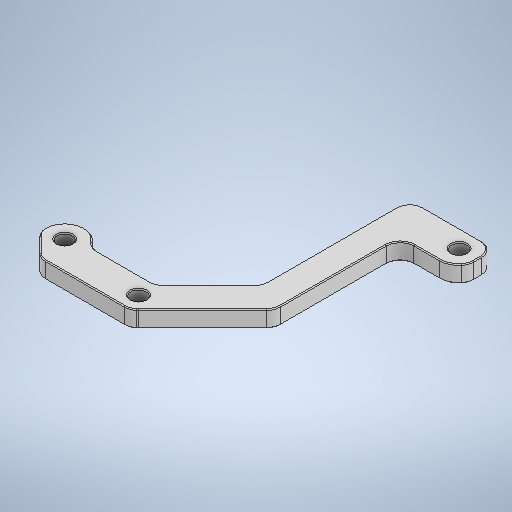
# Autodesk Inventor part: Separator
Saved by Autodesk Inventor 2025.2 (Build 292293000, 293)
## iProperties
Created: 2026-06-16
Part Number: Separator
Material: Generic
Document SubType Name: Modeling
Designer: Bruno
Density: 1 g/cm^3
Appearance: Default
Author: Bruno
## iProperties of the stored document Separator_3DPrint.ipt
Created: 2026-06-26
Part Number: Separator_3DPrint
Material: Generic
Document SubType Name: Modeling
Designer: Bruno
Density: 1 g/cm^3
Appearance: Default
Author: Bruno
Autodesk Inventor part; units mm, degrees
ref_plane "YZ Plane" through (0, 0, 0) normal (1, 0, 0) x (0, 1, 0)
ref_plane "XZ Plane" through (0, 0, 0) normal (0, 1, 0) x (-1, 0, 0)
ref_plane "XY Plane" through (0, 0, 0) normal (0, 0, 1) x (1, 0, 0)
sketch "Sketch1" plane through (0, 0, 0) normal (0, 1, 0) x (-1, 0, 0)
  line L0 (58.4, 33.4) -> (-58.4, 33.4) construction
  line L1 (-58.4, 33.4) -> (-58.4, -33.4)
  line L2 (-58.4, -33.4) -> (58.4, -33.4)
  line L3 (58.4, -33.4) -> (58.4, 33.4)
  line L4 (58.4, 33.4) -> (-58.4, -33.4) construction
  line L5 (-58.4, 33.4) -> (58.4, -33.4) construction
  line L6 (58.4, 33.4) -> (58.4, 88.4)
  line L7 (58.4, 88.4) -> (-58.4, 88.4)
  line L8 (-58.4, 88.4) -> (-58.4, 33.4)
  line L9 (20.8, 25.375) -> (-25.45, 25.375) construction
  line L10 (-25.45, 25.375) -> (-26.8, 24.025) construction
  line L11 (-26.8, 24.025) -> (-26.8, -24.025) construction
  line L12 (-26.8, -24.025) -> (-25.45, -25.375) construction
  line L13 (-25.45, -25.375) -> (20.8, -25.375) construction
  line L14 (20.8, -25.375) -> (26.8, -19.375) construction
  line L15 (26.8, -19.375) -> (26.8, 19.375) construction
  line L16 (26.8, 19.375) -> (20.8, 25.375) construction
  line L17 (0, 0) -> (14.4314, 0) construction
  line L18 (0, 0) -> (0, -12.5097) construction
  line L19 (20.8828, 25.575) -> (-25.5328, 25.575)
  line L20 (-25.5328, 25.575) -> (-27, 24.1078)
  line L21 (-27, 24.1078) -> (-27, -24.1078)
  line L22 (-27, -24.1078) -> (-25.5328, -25.575)
  line L23 (-25.5328, -25.575) -> (20.8828, -25.575)
  line L24 (20.8828, -25.575) -> (27, -19.4578)
  line L25 (27, -19.4578) -> (27, 19.4578) construction
  line L26 (27, 19.4578) -> (20.8828, 25.575)
  arc A0 (-27, -24.1078) -> (-25.5328, -25.575) centre (-25.5328, -24.1078) ccw
  arc A1 (-25.5328, 25.575) -> (-27, 24.1078) centre (-25.5328, 24.1078) ccw
  line L27 (29.5, -16.9578) -> (29.5, 16.9578)
  line L28 (27, -19.4578) -> (29.5, -16.9578)
  line L29 (27, 19.4578) -> (29.5, 16.9578)
  dimension "d0" = 116.8
  dimension "d1" = 66.8
  dimension "d2" = 121.8
  dimension "d6" = 50.75
  dimension "d7" = 53.6
  dimension "d8" = 50.75
  dimension "d9" = 53.6
  dimension "d10" = 45
  dimension "d11" = 48.05
  dimension "d12" = 38.75
  dimension "d13" = 0.2
  dimension "d19" = 2.7
  constraints: 60 end point, 10 perpendicular, 6 parallel, 4 point on circle, 3 equal length, 3 horizontal, 3 vertical, 2 centre point, 2 midpoint, 2 tangent, 1 collinear, 7 other
  measures "d0" distance of L1.end L2.end
  measures "d1" distance between parallel lines of L2 L0
  measures "d2" distance between parallel lines of L2 L7
  measures "d6" distance between parallel lines of L13 L9
  measures "d7" distance between parallel lines of L11 L15
  measures "d8" diameter of L9 L17
  measures "d9" diameter of L15 L18
  measures "d10" angle of L11 L12
  measures "d11" distance of L10.end L11.end
  measures "d12" distance of L14.end L15.end
  measures "d13" distance between parallel lines of L16 L26
  measures "d19" distance between parallel lines of L15 L27
extrude "Extrusion1" add sketch "Sketch1" along normal blind 1.6 contours L8 L7 L6 L3 L2 L1 | L20 A1 | L22 A0
sketch "Sketch2" plane through (0, 0, 0) normal (0, -1, 0) x (1, 0, 0)
  line L0 (58.4, -33.4) -> (-58.4, -33.4) projected
  line L1 (58.4, 88.4) -> (58.4, -33.4) projected
  line L2 (-58.4, 88.4) -> (58.4, 88.4) projected
  line L3 (-58.4, -33.4) -> (-58.4, 88.4) projected
  line L4 (25.5328, -25.575) -> (27, -24.1078) projected
  line L5 (-20.8828, -25.575) -> (25.5328, -25.575) projected
  line L6 (-29.5, -16.9578) -> (-20.8828, -25.575) projected
  line L7 (-29.5, 16.9578) -> (-29.5, -16.9578) projected
  line L8 (-20.8828, 25.575) -> (-29.5, 16.9578) projected
  line L9 (25.5328, 25.575) -> (-20.8828, 25.575) projected
  line L10 (27, 24.1078) -> (25.5328, 25.575) projected
  line L11 (27, -24.1078) -> (27, 24.1078) projected
  line L12 (-21.5456, 27.175) -> (-31.1, 17.6206)
  line L13 (-31.1, 17.6206) -> (-31.1, -17.6206)
  line L14 (-31.1, -17.6206) -> (-21.5456, -27.175)
  line L15 (-21.5456, -27.175) -> (26.1956, -27.175)
  line L16 (26.1956, -27.175) -> (28.6, -24.7706)
  line L17 (28.6, -24.7706) -> (28.6, 24.7706)
  line L18 (28.6, 24.7706) -> (26.1956, 27.175)
  line L19 (26.1956, 27.175) -> (-21.5456, 27.175)
  dimension "d77" = 1.6
  constraints: 16 end point, 7 other
  measures "d77" distance between parallel lines of L9 L19
extrude "Extrusion2" add sketch "Sketch2" along normal blind 25.235 contours L19 L18 L17 L16 L15 L14 L13 L12
sketch "Sketch3" plane through (0, -25.235, 0) normal (0, -1, 0) x (1, 0, 0)
  line L0 (-31.1, 17.6206) -> (-31.1, -17.6206) projected
  line L1 (-31.1, -17.6206) -> (-21.5456, -27.175) projected
  line L2 (-21.5456, -27.175) -> (26.1956, -27.175) projected
  line L3 (26.1956, -27.175) -> (28.6, -24.7706) projected
  line L4 (28.6, -24.7706) -> (28.6, 24.7706) projected
  line L5 (28.6, 24.7706) -> (26.1956, 27.175) projected
  line L6 (26.1956, 27.175) -> (-21.5456, 27.175) projected
  line L7 (-21.5456, 27.175) -> (-31.1, 17.6206) projected
  line L8 (25.5328, -25.575) -> (-20.8828, -25.575) projected
  line L9 (-20.8828, -25.575) -> (-29.5, -16.9578) projected
  line L10 (-29.5, -16.9578) -> (-29.5, 16.9578) projected
  line L11 (-29.5, 16.9578) -> (-20.8828, 25.575) projected
  line L12 (-20.8828, 25.575) -> (25.5328, 25.575) projected
  line L13 (25.5328, 25.575) -> (27, 24.1078) projected
  line L14 (27, 24.1078) -> (27, -24.1078) projected
  line L15 (27, -24.1078) -> (25.5328, -25.575) projected
  point P0 (0, 0)
extrude "Extrusion3" add sketch "Sketch3" along normal blind 1.6 contours L7 L6 L5 L4 L3 L2 L1 L0 | L8 L9 L10 L11 L12 L13 L14 L15
sketch "Sketch4" plane through (0, -26.835, 0) normal (0, -1, 0) x (1, 0, 0)
  line L0 (-31.1, 14.875) -> (-15.8, 14.875)
  line L1 (-15.8, 14.875) -> (-15.8, -0.775)
  line L2 (-15.8, -0.775) -> (-31.1, -0.775)
  line L3 (25.5328, -25.575) -> (-20.8828, -25.575) projected
  line L4 (-20.8828, -25.575) -> (-29.5, -16.9578) projected
  line L5 (-29.5, -16.9578) -> (-29.5, 16.9578) projected
  line L6 (-29.5, 16.9578) -> (-20.8828, 25.575) projected
  line L7 (-20.8828, 25.575) -> (25.5328, 25.575) projected
  line L8 (25.5328, 25.575) -> (27, 24.1078) projected
  line L9 (27, 24.1078) -> (27, -24.1078) projected
  line L10 (27, -24.1078) -> (25.5328, -25.575) projected
  line L11 (-31.1, -17.6206) -> (-21.5456, -27.175) projected
  line L12 (-21.5456, -27.175) -> (26.1956, -27.175) projected
  line L13 (26.1956, -27.175) -> (28.6, -24.7706) projected
  line L14 (28.6, -24.7706) -> (28.6, 24.7706) projected
  line L15 (28.6, 24.7706) -> (26.1956, 27.175) projected
  line L16 (26.1956, 27.175) -> (-21.5456, 27.175) projected
  line L17 (-21.5456, 27.175) -> (-31.1, 17.6206) projected
  line L18 (-31.1, 17.6206) -> (-31.1, -17.6206) projected
  point P0 (0, 0)
  dimension "d78" = 24.8
  dimension "d79" = 13.7
  dimension "d80" = 10.7
  constraints: 6 end point, 1 horizontal, 1 perpendicular
  measures "d78" distance between parallel lines of L3 L2
  measures "d79" distance between parallel lines of L5 L1
  measures "d80" distance between parallel lines of L7 L0
extrude "Extrusion4" cut sketch "Sketch4" against normal blind 9 contours L0 L5 L2 L18 | L0 L1 L2 L5
sketch "Sketch5" plane through (0, -25.235, 0) normal (0, 1, 0) x (1, 0, 0)
  line L0 (-29.5, -16.9578) -> (-29.5, 16.9578) projected
  line L1 (-29.5, 16.9578) -> (-20.8828, 25.575) projected
  line L2 (-20.8828, -25.575) -> (-29.5, -16.9578) projected
  line L3 (25.5328, -25.575) -> (-20.8828, -25.575) projected
  line L4 (27, -24.1078) -> (25.5328, -25.575) projected
  line L5 (27, 24.1078) -> (27, -24.1078) projected
  line L6 (25.5328, 25.575) -> (27, 24.1078) projected
  line L7 (-20.8828, 25.575) -> (25.5328, 25.575) projected
  line L8 (-29.3, 16.875) -> (-29.3, -16.875) construction
  line L9 (-29.3, -16.875) -> (-20.8, -25.375) construction
  line L10 (-20.8, -25.375) -> (25.45, -25.375) construction
  line L11 (25.45, -25.375) -> (26.8, -24.025) construction
  line L12 (26.8, -24.025) -> (26.8, 24.025) construction
  line L13 (26.8, 24.025) -> (25.45, 25.375) construction
  line L14 (25.45, 25.375) -> (-20.8, 25.375) construction
  line L15 (-20.8, 25.375) -> (-29.3, 16.875) construction
  circle A0 centre (22.95, 21.625) radius 4.25
  circle A1 centre (22.95, 21.625) radius 2
  circle A2 centre (-3.05, -21.875) radius 3.8
  circle A3 centre (-3.05, -21.875) radius 2
  circle A4 centre (-21.55, -19.375) radius 4.25
  circle A5 centre (-21.55, -19.375) radius 2
  point P0 (0, 0)
  point P1 (-29.5, -16.8164)
  point P2 (-29.5, 16.8164)
  point P3 (21.3816, 25.575)
  point P4 (27, 20.3366)
  point P5 (-2.184, -25.575)
  point P6 (-3.916, -25.575)
  point P7 (-23.1425, -23.3154)
  point P8 (-25.4904, -20.9675)
  dimension "d28" = 0.2
  dimension "d30" = 4
  dimension "d31" = 3.85
  dimension "d34" = 4
  dimension "d37" = 26
  dimension "d39" = 4
  dimension "d41" = 18.5
  dimension "d43" = 3.75
  dimension "d44" = 3.5
  dimension "d45" = 6
  dimension "d46" = 7.6
  dimension "d47" = 8.5
  dimension "d48" = 8.5
  constraints: 16 end point, 6 centre point, 3 coincident, 9 other
  measures "d28" distance between parallel lines of L0 L8
  measures "d30" diameter of A1
  measures "d31" distance from line of A0.centre L12
  measures "d34" diameter of A3
  measures "d37" horizontal distance of A0.centre A2.centre
  measures "d39" diameter of A5
  measures "d41" horizontal distance of A3.centre A4.centre
  measures "d43" distance from line of L14 A0.centre
  measures "d44" distance from line of L10 A2.centre
  measures "d45" distance from line of L10 A4.centre
  measures "d46" diameter of A2
  measures "d47" diameter of A0
  measures "d48" diameter of A4
extrude "Extrusion5" add sketch "Sketch5" along normal blind 20.015 contours A4 L2 | L7 A0 L5 | L7 L6 L5 A0 | A2 L3 picked at (-23.8933, -21.6613) picked at (-2.9696, -25.0035)
sketch "Sketch6" plane through (0, -25.235, 0) normal (0, 1, 0) x (1, 0, 0)
  circle A0 centre (-21.55, -19.375) radius 2 projected
  circle A1 centre (-3.05, -21.875) radius 2 projected
  circle A2 centre (22.95, 21.625) radius 2 projected
  point P0 (0, 0)
extrude "Extrusion6" add sketch "Sketch6" along normal blind 13.315
sketch "Sketch7" plane through (0, 1.6, 0) normal (0, 1, 0) x (1, 0, 0)
  line L0 (-58.4, 33.4) -> (-58.4, -88.4) projected
  line L1 (-58.4, -88.4) -> (58.4, -88.4) projected
  line L2 (58.4, -88.4) -> (58.4, 33.4) projected
  line L3 (58.4, 33.4) -> (-58.4, 33.4) projected
  point P0 (0, 0)
extrude "Extrusion7" cut sketch "Sketch7" against normal up to surface (1.6 mm away)
sketch "Sketch8" plane through (0, -5.22, 0) normal (0, 1, 0) x (1, 0, 0)
  line L0 (-23.1425, -23.3154) -> (-25.4904, -20.9675) projected
  arc A0 (-23.1425, -23.3154) -> (-25.4904, -20.9675) centre (-21.55, -19.375) ccw projected
  circle A1 centre (-21.55, -19.375) radius 2 projected
  circle A2 centre (-3.05, -21.875) radius 2 projected
  line L1 (-2.184, -25.575) -> (-3.916, -25.575) projected
  arc A3 (-2.184, -25.575) -> (-3.916, -25.575) centre (-3.05, -21.875) ccw projected
  circle A4 centre (-3.05, -21.875) radius 2 projected
  arc A5 (21.3816, 25.575) -> (27, 20.3366) centre (22.95, 21.625) ccw projected
  line L2 (27, 24.1078) -> (27, 20.3366) projected
  line L3 (25.5328, 25.575) -> (27, 24.1078) projected
  line L4 (21.3816, 25.575) -> (25.5328, 25.575) projected
  circle A6 centre (22.95, 21.625) radius 2 projected
  circle A7 centre (-21.55, -19.375) radius 1.65
  circle A8 centre (-3.05, -21.875) radius 1.65
  circle A9 centre (22.95, 21.625) radius 1.65
  arc A10 (-23.1425, -23.3154) -> (-25.4904, -20.9675) centre (-21.55, -19.375) ccw projected
  line L5 (-29.5, -16.9578) -> (-20.8828, -25.575) projected
  line L6 (27, 24.1078) -> (25.5328, 25.575) projected
  line L7 (25.5328, 25.575) -> (-20.8828, 25.575) projected
  line L8 (27, -24.1078) -> (27, 24.1078) projected
  line L9 (-3.05, -18.075) -> (-17.5037, -18.075)
  line L10 (-31.1, 17.6206) -> (-31.1, -17.6206) projected
  line L11 (25.4914, -25.475) -> (-20.8414, -25.475)
  line L12 (-20.8414, -25.475) -> (-29.4, -16.9164)
  line L13 (-29.4, -16.9164) -> (-29.4, 16.9164)
  line L14 (-29.4, 16.9164) -> (-20.8414, 25.475)
  line L15 (-20.8414, 25.475) -> (25.4914, 25.475)
  line L16 (25.4914, 25.475) -> (26.9, 24.0664)
  line L17 (26.9, 24.0664) -> (26.9, -24.0664)
  line L18 (26.9, -24.0664) -> (25.4914, -25.475)
  line L19 (14.4, -9.799) -> (14.4, 17.375)
  line L20 (14.4, 17.375) -> (22.95, 17.375)
  line L21 (-0.363, -24.562) -> (14.4, -9.799)
  line L22 (-3.05, -18.075) -> (8.4, -6.625)
  line L23 (8.4, -6.625) -> (8.4, 25.475)
  line L24 (-31.1, -17.6206) -> (-21.5456, -27.175) projected
  line L25 (-21.5456, -27.175) -> (26.1956, -27.175) projected
  line L26 (26.1956, -27.175) -> (28.6, -24.7706) projected
  line L27 (28.6, -24.7706) -> (28.6, 24.7706) projected
  line L28 (28.6, 24.7706) -> (26.1956, 27.175) projected
  line L29 (26.1956, 27.175) -> (-21.5456, 27.175) projected
  line L30 (-21.5456, 27.175) -> (-31.1, 17.6206) projected
  line L31 (25.5328, -25.575) -> (27, -24.1078) projected
  line L32 (-20.8828, 25.575) -> (-29.5, 16.9578) projected
  line L33 (-20.8828, -25.575) -> (25.5328, -25.575) projected
  line L34 (-29.5, 16.9578) -> (-29.5, -16.9578) projected
  point P0 (0, 0)
  point P1 (-25.574, -20.7424)
  point P2 (-1.8334, -25.475)
  point P3 (26.9, 20.0566)
  dimension "d55" = 3.3
  dimension "d56" = 3.3
  dimension "d57" = 3.3
  dimension "d64" = 45
  dimension "d65" = 12.5
  dimension "d66" = 6
  dimension "d86" = 0.1
  dimension "d87" = 0.1
  dimension "d88" = 0.1
  dimension "d90" = 0.1
  dimension "d91" = 0.1
  dimension "d92" = 0.1
  dimension "d93" = 0.1
  dimension "d94" = 0.1
  constraints: 28 end point, 4 point on circle, 3 centre point, 3 coincident, 3 tangent, 2 horizontal, 1 parallel, 1 perpendicular, 1 point on line, 1 vertical
  measures "d55" diameter of A7
  measures "d56" diameter of A8
  measures "d57" diameter of A9
  measures "d64" angle of L19 L21
  measures "d65" distance between parallel lines of L17 L19
  measures "d66" distance between parallel lines of L23 L19
  measures "d86" distance between parallel lines of L31 L18
  measures "d87" distance between parallel lines of L3 L16
  measures "d88" distance between parallel lines of L32 L14
  measures "d90" distance between parallel lines of L12 L5
  measures "d91" distance between parallel lines of L33 L11
  measures "d92" distance between parallel lines of L8 L17
  measures "d93" distance between parallel lines of L34 L13
  measures "d94" distance between parallel lines of L7 L15
extrude "Extrusion8" add sketch "Sketch8" along normal blind 3.61 contours L12 A0 | A0 L9 A3 L11 L12 | L22 L23 L15 A5 L20 L19 L21 A3 | A3 L11 | L15 L16 L17 A5 | A1 | A2 | A6
sketch "Sketch9" plane through (0, -5.22, 0) normal (0, -1, 0) x (1, 0, 0)
  line L0 (-40.8453, 31.6715) -> (42.4078, 31.6715)
  line L1 (42.4078, 31.6715) -> (42.4078, -33.6664)
  line L2 (42.4078, -33.6664) -> (-40.8453, -33.6664)
  line L3 (-40.8453, -33.6664) -> (-40.8453, 31.6715)
  point P0 (0, 0)
  constraints: 8 end point, 2 parallel, 1 horizontal, 1 perpendicular
extrude "Extrusion9" cut sketch "Sketch9" along normal through all
sketch "Sketch10" plane through (-21.5042, 0, 27.075) normal (0, 1, 0) x (1, 0, 0)
  line L0 (-9.5958, 9.4544) -> (-0.0414, -0.1) projected
  line L1 (-0.0414, -0.1) -> (47.6997, -0.1) projected
  line L2 (47.6997, -0.1) -> (50.1042, 2.3044) projected
  line L3 (50.1042, 2.3044) -> (50.1042, 51.8456) projected
  line L4 (50.1042, 51.8456) -> (47.6997, 54.25) projected
  line L5 (47.6997, 54.25) -> (-0.0414, 54.25) projected
  line L6 (-0.0414, 54.25) -> (-9.5958, 44.6956) projected
  line L7 (-9.5958, 44.6956) -> (-9.5958, 9.4544) projected
  line L8 (47.037, 52.65) -> (0.6213, 52.65) projected
  line L9 (48.5042, 51.1828) -> (47.037, 52.65) projected
  line L10 (48.5042, 2.9672) -> (48.5042, 51.1828) projected
  line L11 (47.037, 1.5) -> (48.5042, 2.9672) projected
  line L12 (0.6213, 1.5) -> (47.037, 1.5) projected
  line L13 (-7.9958, 10.1172) -> (0.6213, 1.5) projected
  line L14 (-7.9958, 44.0328) -> (-7.9958, 10.1172) projected
  line L15 (0.6213, 52.65) -> (-7.9958, 44.0328) projected
  point P0 (21.5042, 27.075)
extrude "Extrusion10" cut sketch "Sketch10" against normal through all
fillet "Fillet1" radius 3 12 edges at (-17.5037, -3.415, 18.075) (-25.574, -3.415, 20.7424) (-20.8414, -3.415, 25.475) (-1.8334, -3.415, 25.475) (-3.05, -3.415, 18.075) (8.4, -3.415, 6.625) (8.4, -3.415, -25.475) (25.4914, -3.415, -25.475) (26.9, -3.415, -24.0664) (26.9, -3.415, -20.0566) (14.4, -3.415, -17.375) (14.4, -3.415, 9.799)
chamfer "Chamfer1" distance 0.2 angle 45 51 edges at (14.4, -5.22, -2.9093) (15.2787, -5.22, -16.4963) (20.175, -5.22, -17.375) (24.7281, -5.22, -17.7648) (26.7142, -5.22, -19.7734) (26.9, -5.22, -21.6443) (26.0216, -5.22, -24.5966) (17.6505, -5.22, -25.475) (9.2787, -5.22, -24.5963) (8.4, -5.22, -8.5463) (8.1716, -5.22, 6.5304) (2.675, -5.22, 12.35) (-3.1446, -5.22, 17.8466) (-10.0027, -5.22, 18.075) (-17.066, -5.22, 17.7525) (-22.7182, -5.22, 15.2887) (-25.6105, -5.22, 20.3167) (-23.3188, -5.22, 22.9976) (-20.7468, -5.22, 25.2466) (-1.4602, -5.22, 25.2812) (6.5792, -5.22, 17.6198) (14.1716, -5.22, 9.7044) (6.5792, -1.61, 17.6198) (14.1716, -1.61, 9.7044) (14.4, -1.61, -2.9093) (15.2787, -1.61, -16.4963) (20.175, -1.61, -17.375) (24.7281, -1.61, -17.7648) (26.7142, -1.61, -19.7734) (26.9, -1.61, -21.6443) (26.0216, -1.61, -24.5966) (17.6505, -1.61, -25.475) (9.2787, -1.61, -24.5963) (8.4, -1.61, -8.5463) (8.1716, -1.61, 6.5304) (2.675, -1.61, 12.35) (-3.1446, -1.61, 17.8466) (-10.0027, -1.61, 18.075) (-17.066, -1.61, 17.7525) (-22.7182, -1.61, 15.2887) (-25.6105, -1.61, 20.3167) (-23.3188, -1.61, 22.9976) (-20.7468, -1.61, 25.2466) (-11.0598, -1.61, 25.475) (-1.4602, -1.61, 25.2812) (-23.2, -1.61, 19.375) (-4.7, -1.61, 21.875) (21.3, -1.61, -21.625) (21.3, -5.22, -21.625) (-4.7, -5.22, 21.875) (-23.2, -5.22, 19.375)
equation "\"d3\" = topbot"
equation "\"d17\" = topbot"
equation "\"walls\" = 1.6"
equation "\"topbot\" = 1.6"
equation "\"insertsD\" = 4.6"
equation "\"d35\" = 4.6"
equation "\"d40\" = 4.6"
body "Solid1"
